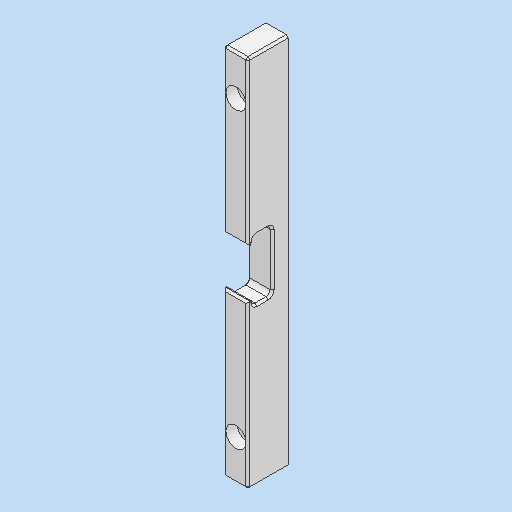
# Autodesk Inventor part: MN0555AN106_G01_101
Saved by Autodesk Inventor 2023.3 (Build 273359000, 359)
## iProperties
RuleStatus: InUse
Created: 2023-03-08
Part Number: MN0555AN106_G01_101
Material: Kst - Pa 6 (weiss)
Description: =<RBPARTNOTITLE2>
Document SubType Name: Modeling
Designer: FH/Wi
Mass: 44.0952 g
Surface Area: 125.055 cm^2
Volume: 38.68 cm^3
Density: 1.14 g/cm^3
Appearance: weiss AnP
AnP_Kategorie: 1
AnP_Material: =<Material>
MaxAbmaße: 186 x 18 x 12 (FM)
AnP_TemplVers: 20200821
RBDOCUMENTTYPE: DRF
RBDOCUMENTVERSION: 00
RBDRAWINGMAINSCALE: 1:1
RBDRAWINGMISSINGSPEC: --
RBDRAWINGVOLUME: --
RBDSV1: 0850
RBGBEDGESIN1: +0,5
RBGBEDGESIN2: +0,2
RBGBEDGESOUT1: -0,3
RBGBEDGESOUT2: -0,1
RBMATERIAL: =<Material>
RBMATMEETS: --
RBMATNO: =<Part Number>
RBPARTMADEOF: 186 x 18 x 12 (FM)
RBPARTNO: SIEHE MNR
RBPARTNOTITLE1: manufactured part
RBPARTNOTITLE2: Anfertigungsteil
RBPARTSAFETYINDICATOR: --
RBSURFACE: --
RBSURFACE2: --
RBZEDGESNORM: ISO13715:2002-06
RBZGENDIMCLASS: m
RBZGENDIMNORM: ISO 2768-1:1989-11
RBZGENGEOCLASS: H
RBZGENGEONORM: ISO 2768-2:1989-11
RBZSURFACENORM: ISO13D2:2002-02
RBZTOLERANCENORM: ISO 14405-1:2010-12
Author: FH/Wi
Keywords: =<RBPARTMADEOF>
Comments: =<RBSURFACE2>
Revision Number: 01
Autodesk Inventor part; units mm, degrees
ref_plane "YZ Plane" through (0, 0, 0) normal (1, 0, 0) x (0, 1, 0)
ref_plane "XZ Plane" through (0, 0, 0) normal (0, 1, 0) x (-1, 0, 0)
ref_plane "XY Plane" through (0, 0, 0) normal (0, 0, 1) x (1, 0, 0)
sketch "Skizze1" plane through (0, 0, 0) normal (0, 0, 1) x (1, 0, 0)
  line L0 (0, 0) -> (-12, 0)
  line L1 (-12, 0) -> (-12, -20)
  line L2 (-12, -20) -> (0, -20)
  line L3 (0, -20) -> (0, 0)
  dimension "d0" = 12
  dimension "d1" = 20
  constraints: 8 end point, 3 perpendicular, 1 horizontal
  measures "d0" distance of L0.start L0.end
  measures "d1" distance of L2.end L0.start
extrude "Extrusion1" add sketch "Skizze1" along normal mid plane 186
sketch "Skizze2" plane through (-12, -20, 93) normal (0, -1, 0) x (1, 0, 0)
  line L0 (12, -93) -> (-0.7686, -93)
  line L1 (0, 0) -> (12, 0) projected
  point P0 (6, -20)
  point P1 (6, -166)
  point P2 (6, 0)
  dimension "d11" = 20
  constraints: 2 end point, 1 horizontal, 1 midpoint, 1 symmetric about line, 1 vertical alignment
  measures "d11" distance of point (6, 0) point (6, -20)
hole "Bohrung1" at (-6, -20, 73) at (-6, -20, -73) direction (0, 1, 0) diameter 5.5 end through all counterbore diameter 10 counterbore depth 5.7 clearance for "Inbusschraube ISO 4762  versenkt" size "M5" standard "ISO"
sketch "Skizze3" plane through (0, -20, 93) normal (1, 0, 0) x (0, 0, -1)
  line L0 (78, 12) -> (108, 12)
  line L1 (108, 12) -> (108, 0)
  line L2 (108, 0) -> (78, 0)
  line L3 (78, 0) -> (78, 12)
  line L4 (186, 20) -> (0, 20) projected
  line L5 (186, 0) -> (0, 0) projected
  line L6 (78, 0) -> (81, 0)
  line L7 (81, 0) -> (81, 2.5)
  line L8 (81, 2.5) -> (78, 2.5)
  line L9 (78, 2.5) -> (78, 0)
  line L10 (108, 0) -> (105, 0)
  line L11 (105, 0) -> (105, 2.5)
  line L12 (105, 2.5) -> (108, 2.5)
  line L13 (108, 2.5) -> (108, 0)
  point P0 (93, 20)
  point P1 (93, 20)
  point P2 (93, 12)
  point P3 (78, 2.5)
  point P4 (81, 0)
  point P5 (105, 0)
  point P6 (108, 2.5)
  dimension "d12" = 30
  dimension "d16" = 8
  dimension "d26" = 3
  dimension "d27" = 3
  dimension "d28" = 2.5
  constraints: 24 end point, 6 parallel, 3 horizontal, 3 perpendicular, 2 midpoint, 2 point on line, 1 vertical alignment
  measures "d12" distance of L0.start L0.end
  measures "d16" distance between parallel lines of L0 L4
  measures "d26" distance of L7.end L8.end
  measures "d27" distance of L11.end L12.end
  measures "d28" distance between parallel lines of L6 L8
extrude "Extrusion2" cut sketch "Skizze3" against normal through all contours L0 L1 L12 L11 L2 L7 L8 L3
fillet "Rundung1" radius 2 4 edges at (-6, -8, 15) (-6, -8, -15) (-6, -17.5, -15) (-6, -17.5, 15)
chamfer "Fase1" distance 1 angle 45 32 edges at (0, -10, 93) (-6, -20, 93) (-12, -10, 93) (-12, -20, -52.5) (-12, -20, 52.5) (0, -20, -52.5) (0, -20, 52.5) (-12, -12.75, 15) (-12, -16.9142, 14.4142) (-12, -17.5, 12.5) (-12, -8.5858, 14.4142) (-12, -8, 0) (-12, -8.5858, -14.4142) (-12, -12.75, -15) (-12, -16.9142, -14.4142) (-12, -17.5, -12.5) (0, -12.75, 15) (0, -8.5858, 14.4142) (0, -8, 0) (0, -8.5858, -14.4142) (0, -12.75, -15) (0, -16.9142, -14.4142) (0, -17.5, -12.5) (0, -16.9142, 14.4142) (0, -17.5, 12.5) (-6, -17.5, 12) (-6, -20, 12) (-6, -17.5, -12) (-6, -20, -12) (0, -10, -93) (-12, -10, -93) (-6, -20, -93)
equation "\"d27\" = d26"
